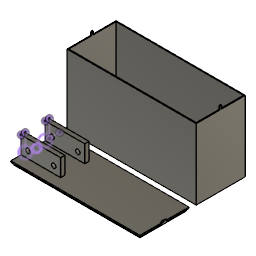
Czujniki-SeedIoT (Autodesk Fusion 360 design; units mm, degrees)
part number: 2026-04-24-13-22-16-515
Autodesk Fusion 360 part; units mm, degrees
sketch "Sketch1" plane through (0, 0, 0) normal (0, 0, 1) x (1, 0, 0)
  line L0 (75, 28.5) -> (-75, 28.5)
  line L1 (-75, 28.5) -> (-75, -28.5)
  line L2 (-75, -28.5) -> (75, -28.5)
  line L3 (75, -28.5) -> (75, 28.5)
  line L4 (75, 28.5) -> (-75, -28.5) construction
  line L5 (-75, 28.5) -> (75, -28.5) construction
  dimension "d3" = 57
  dimension "d4" = 150
  constraint horizontal L0
  constraint perpendicular L0 L1
  constraint parallel L0 L2
  constraint parallel L1 L3
  constraint coincident L4 origin
  constraint coincident L5 origin
  measures "d3" distance of L0.end L1.end
  measures "d4" distance of L0.start L0.end
extrude "Extrude1" add sketch "Sketch1" along normal blind 4 makes body 1
sketch "Sketch2" plane through (0, 0, 4) normal (0, 0, 1) x (-1, 0, 0)
  line L0 (-75, 28.5) -> (-75, -28.5)
  line L1 (-75, -28.5) -> (75, -28.5)
  line L2 (75, -28.5) -> (75, 28.5)
  line L3 (75, 28.5) -> (-75, 28.5)
  line L4 (29, 11.5) -> (75, 11.5)
  line L5 (75, 11.5) -> (75, -11.5)
  line L6 (75, -11.5) -> (29, -11.5)
  line L7 (29, -11.5) -> (29, 11.5)
  line L8 (29, 11.5) -> (75, -11.5) construction
  line L9 (75, 11.5) -> (29, -11.5) construction
  line L10 (75, -11.5) -> (29, -11.5)
  line L11 (29, -11.5) -> (29, -16.5)
  line L12 (29, -16.5) -> (75, -16.5)
  line L13 (75, -16.5) -> (75, -11.5)
  line L14 (75, 11.5) -> (29, 11.5)
  line L15 (29, 11.5) -> (29, 16.5)
  line L16 (29, 16.5) -> (75, 16.5)
  line L17 (75, 16.5) -> (75, 11.5)
  point P0 (75, 0)
  dimension "d7" = 23
  dimension "d8" = 46
  dimension "d9" = 5
  dimension "d10" = 5
  constraint horizontal L4
  constraint perpendicular L4 L5
  constraint parallel L4 L6
  constraint parallel L5 L7
  constraint horizontal L10
  constraint vertical L11
  constraint horizontal L12
  constraint vertical L13
  constraint horizontal L14
  constraint vertical L15
  constraint horizontal L16
  constraint vertical L17
  constraint coincident L6.end L11
  constraint coincident L7 L4.start
  constraint coincident L5 P0
  constraint coincident L2 P0
  measures "d7" distance of L4.start L6.end
  measures "d8" distance of L4.start L4.end
  measures "d9" distance of L6 L12
  measures "d10" distance of L4 L16
extrude "Extrude2" add sketch "Sketch2" along normal blind 20 contours L2 L4 L14 L15 L16 L17 | L2 L6 L10 L11 L12 L13 bodies 1
sketch "Sketch3" plane through (0, -16.5, 0) normal (0, -1, 0) x (1, 0, 0)
  line L0 (-75, 4) -> (-29, 4)
  line L1 (-29, 4) -> (-29, 24)
  line L2 (-29, 24) -> (-75, 24)
  line L3 (-75, 24) -> (-75, 4)
  circle A0 centre (-67, 12) radius 2.6
  circle A1 centre (-37, 12) radius 2.6
  dimension "d13" = 8
  dimension "d14" = 8
  dimension "d15" = 8
  dimension "d16" = 8
  dimension "d17" = 5.2
  dimension "d18" = 5.2
  measures "d13" distance of L0 A0.centre
  measures "d14" distance of L3 A0.centre
  measures "d15" distance of L1 A1.centre
  measures "d16" distance of L0 A1.centre
  measures "d17" diameter of A0
  measures "d18" diameter of A1
extrude "Extrude3" cut sketch "Sketch3" against normal blind 5 contours A0 | A1 bodies 1
sketch "Sketch4" plane through (0, 16.5, 0) normal (0, 1, 0) x (-1, 0, 0)
  line L0 (29, 4) -> (75, 4)
  line L1 (75, 4) -> (75, 24)
  line L2 (75, 24) -> (29, 24)
  line L3 (29, 24) -> (29, 4)
  circle A0 centre (37, 12) radius 2.6
  circle A1 centre (67, 12) radius 2.6
  dimension "d21" = 8
  dimension "d22" = 8
  dimension "d23" = 8
  dimension "d24" = 8
  dimension "d25" = 5.2
  dimension "d26" = 5.2
  measures "d21" distance of L3 A0.centre
  measures "d22" distance of L0 A0.centre
  measures "d23" distance of L1 A1.centre
  measures "d24" distance of L0 A1.centre
  measures "d25" diameter of A0
  measures "d26" diameter of A1
extrude "Extrude4" cut sketch "Sketch4" against normal blind 5 contours A0 | A1 bodies 1
sketch "Sketch5" plane through (0, 0, 0) normal (0, 0, -1) x (1, 0, 0)
  line L0 (75, -28.5) -> (75, 28.5)
  line L1 (75, 28.5) -> (-75, 28.5)
  line L2 (-75, 28.5) -> (-75, -28.5)
  line L3 (-75, -28.5) -> (75, -28.5)
  line L4 (-73.5, -27) -> (73.5, -27)
  line L5 (73.5, -27) -> (73.5, 27)
  line L6 (73.5, 27) -> (-73.5, 27)
  line L7 (-73.5, 27) -> (-73.5, -27)
  line L8 (-73.5, -27) -> (73.5, 27) construction
  line L9 (73.5, -27) -> (-73.5, 27) construction
  dimension "d29" = 1.5
  dimension "d30" = 1.5
  constraint horizontal L4
  constraint perpendicular L4 L5
  constraint parallel L4 L6
  constraint parallel L5 L7
  constraint coincident L8 origin
  constraint coincident L9 origin
  measures "d29" distance of L3 L4
  measures "d30" distance of L2 L7
extrude "Extrude5" cut sketch "Sketch5" against normal blind 2.5 bodies 1
sketch "Sketch6" plane through (-75, 0, 0) normal (-1, 0, 0) x (0, -1, 0)
  line L0 (-28.5, 2.5) -> (28.5, 2.5)
  line L1 (28.5, 2.5) -> (28.5, 4)
  line L2 (28.5, 4) -> (16.5, 4)
  line L3 (-28.5, 4) -> (-28.5, 2.5)
  line L4 (16.5, 4) -> (16.5, 24)
  line L5 (16.5, 24) -> (11.5, 24)
  line L6 (11.5, 24) -> (11.5, 4)
  line L7 (-11.5, 4) -> (-11.5, 24)
  line L8 (-11.5, 24) -> (-16.5, 24)
  line L9 (-16.5, 24) -> (-16.5, 4)
  line L10 (-16.5, 4) -> (-28.5, 4)
sketch "Sketch7" plane through (75, 0, 0) normal (1, 0, 0) x (0, 1, 0)
  line L0 (-28.5, 2.5) -> (28.5, 2.5)
  line L1 (28.5, 2.5) -> (28.5, 4)
  line L2 (28.5, 4) -> (-28.5, 4)
  line L3 (-28.5, 4) -> (-28.5, 2.5)
  line L4 (-3, 4) -> (3, 4)
  line L5 (3, 4) -> (3, 0)
  line L6 (3, 0) -> (-3, 0)
  line L7 (-3, 0) -> (-3, 4)
  dimension "d33" = 4
  dimension "d34" = 6
  constraint horizontal L4
  constraint vertical L5
  constraint horizontal L6
  constraint vertical L7
  constraint coincident L2 L4.start
  measures "d33" distance of L4 L6
  measures "d34" distance of L5 L7
extrude "Extrude6" cut sketch "Sketch7" against normal blind 1.5 contours L0 L2 L4 L5 L7 | L0 L5 L6 L7 bodies 1
sketch "Sketch8" plane through (73.5, 0, 0) normal (1, 0, 0) x (0, 1, 0)
  line L0 (-27, 0) -> (27, 0)
  line L1 (27, 0) -> (27, 2.5)
  line L2 (27, 2.5) -> (3, 2.5)
  line L3 (3, 2.5) -> (3, 4)
  line L4 (3, 4) -> (-3, 4)
  line L5 (-3, 4) -> (-3, 2.5)
  line L6 (-3, 2.5) -> (-27, 2.5)
  line L7 (-27, 2.5) -> (-27, 0)
  line L8 (-1, 3.5) -> (1, 3.5)
  line L9 (1, 3.5) -> (1, 2.5)
  line L10 (1, 2.5) -> (-1, 2.5)
  line L11 (-1, 2.5) -> (-1, 3.5)
  dimension "d37" = 0.5
  dimension "d38" = 2
  dimension "d39" = 2
  dimension "d40" = 1
  constraint horizontal L8
  constraint vertical L9
  constraint horizontal L10
  constraint vertical L11
  measures "d37" distance of L4 L8
  measures "d38" distance of L3 L9
  measures "d39" distance of L5 L11
  measures "d40" distance of L8 L10
extrude "Extrude7" cut sketch "Sketch8" against normal blind 1 contours L8 L9 L10 L11 bodies 1
sketch "Sketch9" plane through (-75, 0, 0) normal (-1, 0, 0) x (0, -1, 0)
  line L0 (-3, 4) -> (3, 4)
  line L1 (3, 4) -> (3, 0)
  line L2 (3, 0) -> (-3, 0)
  line L3 (-3, 0) -> (-3, 4)
  line L4 (11.5, 4) -> (-11.5, 4)
  line L5 (27, 0) -> (-27, 0)
  line L6 (-27, 0) -> (-27, 2.5)
  dimension "d44" = 6
  dimension "d45" = 24
  constraint horizontal L0
  constraint vertical L1
  constraint horizontal L2
  constraint vertical L3
  constraint coincident L0.start L4
  constraint coincident L1.end L5
  measures "d44" distance of L1 L3
  measures "d45" distance of L3 L6
extrude "Extrude8" cut sketch "Sketch9" against normal blind 1.5 bodies 1
sketch "Sketch10" plane through (-73.5, 0, 0) normal (-1, 0, 0) x (0, -1, 0)
  line L0 (-3, 2.5) -> (-27, 2.5)
  line L1 (-27, 2.5) -> (-27, 0)
  line L2 (-27, 0) -> (27, 0)
  line L3 (27, 0) -> (27, 2.5)
  line L4 (27, 2.5) -> (3, 2.5)
  line L5 (3, 2.5) -> (3, 4)
  line L6 (3, 4) -> (-3, 4)
  line L7 (-3, 4) -> (-3, 2.5)
  line L8 (-1, 3.5) -> (1, 3.5)
  line L9 (1, 3.5) -> (1, 2.5)
  line L10 (1, 2.5) -> (-1, 2.5)
  line L11 (-1, 2.5) -> (-1, 3.5)
  line L12 (11.5, 4) -> (-11.5, 4)
  dimension "d48" = 0.5
  dimension "d49" = 2
  dimension "d50" = 2
  dimension "d51" = 1
  constraint horizontal L8
  constraint vertical L9
  constraint horizontal L10
  constraint vertical L11
  measures "d48" distance of L8 L12
  measures "d49" distance of L5 L9
  measures "d50" distance of L7 L11
  measures "d51" distance of L8 L10
extrude "Extrude9" cut sketch "Sketch10" against normal blind 1 contours L8 L9 L10 L11 bodies 1
sketch "Sketch11" plane through (0, 0, 0) normal (0, 0, 1) x (1, 0, 0)
  line L0 (-76.6426, 95.5) -> (73.3574, 95.5)
  line L1 (73.3574, 95.5) -> (73.3574, 38.5)
  line L2 (73.3574, 38.5) -> (-76.6426, 38.5)
  line L3 (-76.6426, 38.5) -> (-76.6426, 95.5)
  line L4 (75, 28.5) -> (-75, 28.5)
  dimension "d54" = 150
  dimension "d55" = 57
  dimension "d56" = 10
  constraint horizontal L0
  constraint vertical L1
  constraint horizontal L2
  constraint vertical L3
  measures "d54" distance of L1 L3
  measures "d55" distance of L0 L2
  measures "d56" distance of L2 L4
extrude "Extrude10" add sketch "Sketch11" along normal blind 2 separate body makes body 2
sketch "Sketch13" plane through (0, 0, 2) normal (0, 0, 1) x (-1, 0, 0)
  line L0 (76.6426, -38.5) -> (-73.3574, -38.5)
  line L1 (-73.3574, -38.5) -> (-73.3574, -95.5)
  line L2 (-73.3574, -95.5) -> (76.6426, -95.5)
  line L3 (76.6426, -95.5) -> (76.6426, -38.5)
  line L4 (-72.3574, -39.5) -> (75.6426, -39.5)
  line L5 (75.6426, -39.5) -> (75.6426, -94.5)
  line L6 (75.6426, -94.5) -> (-72.3574, -94.5)
  line L7 (-72.3574, -94.5) -> (-72.3574, -39.5)
  dimension "d66" = 1
  dimension "d67" = 1
  dimension "d68" = 1
  dimension "d69" = 1
  constraint horizontal L4
  constraint vertical L5
  constraint horizontal L6
  constraint vertical L7
  measures "d66" distance of L0 L4
  measures "d67" distance of L1 L7
  measures "d68" distance of L2 L6
  measures "d69" distance of L3 L5
extrude "Extrude12" add sketch "Sketch13" along normal blind 80 bodies 2
sketch "Sketch15" plane through (0, 0, 82) normal (0, 0, 1) x (-1, 0, 0)
  line L0 (75.6426, -94.5) -> (-72.3574, -94.5)
  line L1 (-72.3574, -94.5) -> (-72.3574, -39.5)
  line L2 (-72.3574, -39.5) -> (75.6426, -39.5)
  line L3 (75.6426, -39.5) -> (75.6426, -94.5)
  line L4 (76.6426, -95.5) -> (76.6426, -38.5)
  line L5 (76.6426, -38.5) -> (-73.3574, -38.5)
  line L6 (-73.3574, -38.5) -> (-73.3574, -95.5)
  line L7 (-73.3574, -95.5) -> (76.6426, -95.5)
  line L8 (75.6426, -66) -> (76.6426, -66)
  line L9 (76.6426, -66) -> (76.6426, -68)
  line L10 (76.6426, -68) -> (75.6426, -68)
  line L11 (75.6426, -68) -> (75.6426, -66)
  line L12 (-73.3574, -66) -> (-72.3574, -66)
  line L13 (-72.3574, -66) -> (-72.3574, -68)
  line L14 (-72.3574, -68) -> (-73.3574, -68)
  line L15 (-73.3574, -68) -> (-73.3574, -66)
  dimension "d73" = 2
  dimension "d74" = 27.5
  dimension "d75" = 2
  dimension "d76" = 27.5
  constraint horizontal L8
  constraint vertical L9
  constraint horizontal L10
  constraint vertical L11
  constraint coincident L4 L9.end
  constraint coincident L3 L8.start
  constraint horizontal L12
  constraint vertical L13
  constraint horizontal L14
  constraint vertical L15
  constraint coincident L1 L13.end
  constraint coincident L6 L12.start
  measures "d73" distance of L8 L10
  measures "d74" distance of L5 L8
  measures "d75" distance of L12 L14
  measures "d76" distance of L5 L12
extrude "Extrude13" add sketch "Sketch15" along normal blind 4 contours L3 L4 L8 L9 L10 L11 | L1 L6 L12 L13 L14 L15 bodies 2
sketch "Sketch18" plane through (72.3574, 0, 0) normal (-1, 0, 0) x (0, -1, 0)
  line L0 (-94.5, 2) -> (-39.5, 2)
  line L1 (-39.5, 2) -> (-39.5, 82)
  line L2 (-39.5, 82) -> (-66, 82)
  line L3 (-66, 82) -> (-66, 86)
  line L4 (-66, 86) -> (-68, 86)
  line L5 (-68, 86) -> (-68, 82)
  line L6 (-68, 82) -> (-94.5, 82)
  line L7 (-94.5, 82) -> (-94.5, 2)
  line L8 (-67.9, 85.5) -> (-66.1, 85.5)
  line L9 (-66.1, 85.5) -> (-66.1, 85)
  line L10 (-66.1, 85) -> (-67.9, 85)
  line L11 (-67.9, 85) -> (-67.9, 85.5)
  dimension "d85" = 0.5
  dimension "d86" = 0.5
  dimension "d88" = 1.8
  dimension "d89" = 0.1
  constraint horizontal L8
  constraint vertical L9
  constraint horizontal L10
  constraint vertical L11
  measures "d85" distance of L4 L8
  measures "d86" distance of L8.end L9.end
  measures "d88" distance of L8.start L8.end
  measures "d89" distance of L5 L11
extrude "Extrude14" add sketch "Sketch18" along normal blind 0.6 contours L8 L9 L10 L11 bodies 2
chamfer "Chamfer1" distance 0.4 angle 45 1 edges at (71.7574, 67, 85.5) on bodies 2
sketch "Sketch19" plane through (-75.6426, 0, 0) normal (1, 0, 0) x (0, 1, 0)
  line L0 (39.5, 2) -> (94.5, 2)
  line L1 (94.5, 2) -> (94.5, 82)
  line L2 (94.5, 82) -> (68, 82)
  line L3 (68, 82) -> (68, 86)
  line L4 (68, 86) -> (66, 86)
  line L5 (66, 86) -> (66, 82)
  line L6 (66, 82) -> (39.5, 82)
  line L7 (39.5, 82) -> (39.5, 2)
  line L8 (66.1, 85.6) -> (67.9, 85.6)
  line L9 (67.9, 85.6) -> (67.9, 85.2)
  line L10 (67.9, 85.2) -> (66.1, 85.2)
  line L11 (66.1, 85.2) -> (66.1, 85.6)
  dimension "d93" = 0.1
  dimension "d94" = 0.1
  dimension "d95" = 0.4
  dimension "d96" = 0.4
  constraint horizontal L8
  constraint vertical L9
  constraint horizontal L10
  constraint vertical L11
  measures "d93" distance of L5 L11
  measures "d94" distance of L3 L9
  measures "d95" distance of L4 L8
  measures "d96" distance of L8 L10
extrude "Extrude15" add sketch "Sketch19" along normal blind 0.6 contours L8 L9 L10 L11 bodies 2
sketch "Sketch20" plane through (-73.5, 0, 0) normal (-1, 0, 0) x (0, -1, 0)
  line L0 (1, 2.5) -> (-1, 2.5)
  line L1 (-1, 3.5) -> (1, 3.5)
  line L2 (-3, 2.5) -> (-27, 2.5)
  line L3 (-27, 2.5) -> (-27, 0)
  line L4 (-27, 0) -> (27, 0)
  line L5 (27, 0) -> (27, 2.5)
  line L6 (27, 2.5) -> (3, 2.5)
  line L7 (3, 2.5) -> (3, 4)
  line L8 (3, 4) -> (-3, 4)
  line L9 (-3, 4) -> (-3, 2.5)
chamfer "Chamfer3" distance 0.4 angle 45 1 edges at (-75.0426, 67, 85.6) on bodies 2
